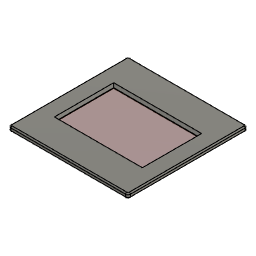
analog_projector (Autodesk Fusion 360 archive; units mm, degrees)
design "Film"
Autodesk Fusion 360 part; units mm, degrees
sketch "Sketch1" plane through (0, 0, 0) normal (0, 0, 1) x (1, 0, 0)
  line L0 (25, -25) -> (-25, -25)
  line L1 (-25, -25) -> (-25, 25)
  line L2 (-25, 25) -> (25, 25)
  line L3 (25, 25) -> (25, -25)
  line L4 (25, -25) -> (-25, 25) construction
  line L5 (-25, -25) -> (25, 25) construction
  dimension "d1" = 50
  dimension "d2" = 50
  constraint horizontal L0
  constraint perpendicular L0 L1
  constraint parallel L0 L2
  constraint parallel L1 L3
  constraint coincident L4 origin
  constraint coincident L5 origin
  measures "d1" distance of L1.end L2.end
  measures "d2" distance of L0.end L1.end
extrude "Extrude1" add sketch "Sketch1" along normal mid plane 2 makes body 1
sketch "Sketch2" plane through (0, 0, 1) normal (0, 0, 1) x (-1, 0, 0)
  line L0 (-25, -25) -> (25, -25)
  line L1 (25, -25) -> (25, 25)
  line L2 (25, 25) -> (-25, 25)
  line L3 (-25, 25) -> (-25, -25)
  line L4 (-17.5, 11.5) -> (17.5, 11.5)
  line L5 (17.5, 11.5) -> (17.5, -11.5)
  line L6 (17.5, -11.5) -> (-17.5, -11.5)
  line L7 (-17.5, -11.5) -> (-17.5, 11.5)
  line L8 (-17.5, 11.5) -> (17.5, -11.5) construction
  line L9 (17.5, 11.5) -> (-17.5, -11.5) construction
  dimension "d5" = 35
  dimension "d6" = 23
  constraint horizontal L4
  constraint perpendicular L4 L5
  constraint parallel L4 L6
  constraint parallel L5 L7
  constraint coincident L8 origin
  constraint coincident L9 origin
  measures "d5" distance of L5.end L6.end
  measures "d6" distance of L4.end L5.end
extrude "Extrude2" cut sketch "Sketch2" against normal up to surface (2 mm away) contours L4 L5 L6 L7 bodies 1
sketch "Sketch3" plane through (0, 0, 0) normal (0, 0, 1) x (1, 0, 0)
  line L0 (17.5, 11.5) -> (17.5, -11.5)
  line L1 (17.5, -11.5) -> (-17.5, -11.5)
  line L2 (-17.5, -11.5) -> (-17.5, 11.5)
  line L3 (-17.5, 11.5) -> (17.5, 11.5)
  line L4 (25, 25) -> (-25, 25)
  line L5 (-25, 25) -> (-25, -25)
  line L6 (-25, -25) -> (25, -25)
  line L7 (25, -25) -> (25, 25)
extrude "Extrude3" add sketch "Sketch3" along normal mid plane 0.2 separate body contours L0 L1 L2 L3 makes body 2
chamfer "Chamfer1" distance 0.9 angle 45 8 edges at (0, -11.5, -1) (17.5, 0, -1) (0, 11.5, -1) (-17.5, 0, -1) (0, -11.5, 1) (17.5, 0, 1) (-17.5, 0, 1) (0, 11.5, 1) on bodies 1
fillet "Fillet1" radius 1 4 edges at (25, -25, 0) (25, 25, 0) (-25, 25, 0) (-25, -25, 0) on bodies 1
fillet "Fillet2" radius 0.5 16 edges at (-24.7071, -24.7071, 1) (0, -25, 1) (24.7071, -24.7071, 1) (25, 0, 1) (24.7071, 24.7071, 1) (0, 25, 1) (-24.7071, 24.7071, 1) (-25, 0, 1) (-24.7071, 24.7071, -1) (0, 25, -1) (24.7071, 24.7071, -1) (25, 0, -1) (24.7071, -24.7071, -1) (0, -25, -1) (-24.7071, -24.7071, -1) (-25, 0, -1) on bodies 1

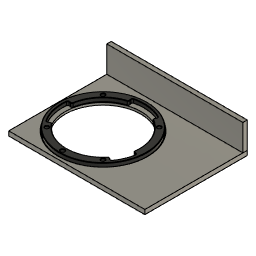
design "Lens Bracket" references "bantam tools desktop cnc milling machine"
Autodesk Fusion 360 part; units mm, degrees
sketch "Sketch1" plane through (0, 0, 0) normal (0, 0, 1) x (1, 0, 0) in component "Corner Bracket"
  line L0 (0, 0) -> (101, 0)
  line L1 (101, 0) -> (101, 76)
  line L2 (101, 76) -> (0, 76)
  line L3 (0, 76) -> (0, 0)
  dimension "d1" = 101
  dimension "d2" = 76
  constraint horizontal L0
  constraint vertical L1
  constraint horizontal L2
  constraint vertical L3
  constraint coincident L0.start L3.end
  measures "d1" distance of L0.start L0.end
  measures "d2" distance of L0.start L2.end
extrude "Extrude1" add sketch "Sketch1" along normal blind 3.3 makes body 1 in component "Corner Bracket"
sketch "Sketch2" plane through (0, 0, 3.3) normal (0, 0, 1) x (-1, 0, 0) in component "Corner Bracket"
  line L0 (0, -76) -> (0, 0)
  line L1 (0, 0) -> (-101, 0)
  line L2 (-101, 0) -> (-101, -76)
  line L3 (-101, -76) -> (0, -76)
  line L4 (0, -76) -> (-101, -76)
  line L5 (-101, -76) -> (-101, -72.75)
  line L6 (-101, -72.75) -> (0, -72.75)
  line L7 (0, -72.75) -> (0, -76)
  dimension "d5" = 3.25
  constraint horizontal L4
  constraint vertical L5
  constraint horizontal L6
  constraint vertical L7
  constraint coincident L2 L5.end
  constraint coincident L0.start L3.end
  measures "d5" distance of L4 L6
extrude "Extrude2" add sketch "Sketch2" along normal blind 19.5 contours L0 L2 L3 L4 L5 L6 L7 bodies 1 in component "Corner Bracket"
sketch "Sketch3" plane through (0, 0, 3.3) normal (0, 0, 1) x (-1, 0, 0) in component "Corner Bracket"
  line L0 (-101, -72.75) -> (0, -72.75)
  line L1 (0, -72.75) -> (0, 0)
  line L2 (0, 0) -> (-101, 0)
  line L3 (-101, 0) -> (-101, -72.75)
  circle A0 centre (-35, -35) radius 28.1
  line L4 (0, -69.5) -> (-101, -69.5)
  dimension "d8" = 56.2
  dimension "d9" = 3.25
  dimension "d10" = 34.5
  dimension "d11" = 35
  dimension "d13" = 35
  constraint coincident L1 L4.start
  constraint coincident L3 L4.end
  constraint perpendicular L3 L4
  measures "d8" diameter of A0
  measures "d9" distance of L0 L4
  measures "d10" distance of A0.centre L4
  measures "d11" distance of L2 A0.centre
  measures "d13" distance of L1 A0.centre
extrude "Extrude3" cut sketch "Sketch3" against normal up to surface (3.3 mm away) contours A0 bodies 1 in component "Corner Bracket"
sketch "Sketch4" plane through (0, 0, 3.3) normal (0, 0, 1) x (-1, 0, 0) in component "Corner Bracket"
  circle A0 centre (-35, -35) radius 28.1
  line L0 (-101, -72.75) -> (0, -72.75)
  line L1 (0, -72.75) -> (0, 0)
  line L2 (0, 0) -> (-101, 0)
  line L3 (-101, 0) -> (-101, -72.75)
  line L4 (-35, -35) -> (-35, 0) construction
  circle A1 centre (-35, -5) radius 1.25
  line L5 (-35, -35) -> (-6.7157, -6.7157) construction
  line L6 (-35, -35) -> (15, -35) construction
  circle A2 centre (-14.1403, -14.1403) radius 1.15
  dimension "d16" = 2.5
  dimension "d17" = 30
  dimension "d18" = 45
  dimension "d19" = 40
  dimension "d20" = 2.3
  dimension "d21" = 29.5
  constraint coincident A0.centre L4.start
  constraint coincident L2 L4.end
  constraint perpendicular L2 L4
  constraint coincident L4 A1.centre
  constraint horizontal L6
  constraint coincident L5 A2.centre
  measures "d16" diameter of A1
  measures "d17" distance of A0.centre A1.centre
  measures "d18" angle of L5 L6
  measures "d19" distance of A0.centre L5.end
  measures "d20" diameter of A2
  measures "d21" distance of A0.centre A2.centre
extrude "Extrude4" cut sketch "Sketch4" against normal up to surface (3.3 mm away) contours A1 | A2 bodies 1 in component "Corner Bracket"
pattern_circular "C-Pattern1" count 4 over 360 about axis through (35, 35, 3.3) along (0, 0, -1) of 1 faces at (12.9918, 14.1977, 1.1) on bodies 1 in component "Corner Bracket"
sketch "Sketch5" plane through (0, 0, 3.3) normal (0, 0, 1) x (-1, 0, 0) in component "Corner Bracket"
  circle A0 centre (-55.8597, -14.1403) radius 1.15
  circle A1 centre (-55.8597, -55.8597) radius 1.15
  circle A2 centre (-14.1403, -55.8597) radius 1.15
  circle A3 centre (-35, -5) radius 1.25
  circle A4 centre (-14.1403, -14.1403) radius 1.15
  circle A5 centre (-35, -35) radius 28.1
  line L0 (-101, -72.75) -> (0, -72.75)
  line L1 (0, -72.75) -> (0, 0)
  line L2 (0, 0) -> (-101, 0)
  line L3 (-101, 0) -> (-101, -72.75)
  circle A6 centre (-35, -35) radius 33
  dimension "d26" = 66
  constraint concentric A5 A6
  measures "d26" diameter of A6
extrude "Extrude5" cut sketch "Sketch5" against normal blind 1.6 contours A6 bodies 1 in component "Corner Bracket"
split "Split1" by plane through (0, 0, 3.3) normal (0, 0, 1) bodies 1 makes body 2 at (67.3333, 76, 9.8) in component "Corner Bracket"
ref_plane "WorkPlane1" through (35, 35, 2.7) normal (0, 0, 1) x (-1, 0, 0) in component "Corner Bracket"
sketch "Sketch6" plane through (35, 35, 2.7) normal (0, 0, 1) x (1, 0, 0) in component "Corner Bracket"
  circle A0 centre (20.8597, 20.8597) radius 1.15
  circle A1 centre (20.8597, -20.8597) radius 1.15
  circle A2 centre (0, -30) radius 1.25
  circle A3 centre (-20.8597, -20.8597) radius 1.15
  circle A4 centre (0, 0) radius 28.1
  circle A5 centre (-20.8597, 20.8597) radius 1.15
  circle A6 centre (0, 0) radius 33
  circle A7 centre (0, 0) radius 32.5
  circle A8 centre (0, 0) radius 27.1
  dimension "d30" = -0.5
  dimension "d31" = -1
extrude "Extrude6" add sketch "Sketch6" along normal blind 3 separate body contours A4 | A7 makes body 3 in component "Corner Bracket"
move_face "OffsetFaces1" offset -0.1 5 faces at (56.3326, 15.1886, 4.7) (36.2484, 4.9377, 4.7) (15.2889, 14.083, 4.7) (15.2889, 55.8023, 4.7) (54.7452, 55.5759, 4.7) on bodies 3 in component "Corner Bracket"
sketch "Sketch7" plane through (0, 0, 5.7) normal (0, 0, 1) x (-1, 0, 0) in component "Corner Bracket"
  circle A0 centre (-14.1403, -55.8597) radius 1.25
  circle A1 centre (-14.1403, -14.1403) radius 1.25
  circle A2 centre (-55.8597, -55.8597) radius 1.25
  circle A3 centre (-35, -35) radius 27.1
  circle A4 centre (-35, -5) radius 1.35
  circle A5 centre (-55.8597, -14.1403) radius 1.25
  circle A6 centre (-35, -35) radius 32.5
  circle A7 centre (-35, -35) radius 30.25
  line L0 (-35, -35) -> (-51, -35) construction
  line L1 (-35, -35) -> (-64.8478, -30.0836)
  line L2 (-35, -35) -> (-58.8625, -16.4085)
  line L3 (-35, -35) -> (-10.4096, -17.3825)
  line L4 (-35, -35) -> (-5.007, -38.9345)
  line L5 (-35, -35) -> (-27.1908, -64.2246)
  line L6 (-35, -35) -> (-49.3044, -61.6542)
  dimension "d35" = 60.5
  dimension "d36" = 61.779
  dimension "d37" = 104.961
  dimension "d38" = 172.527
  dimension "d39" = 144.381
  dimension "d40" = 9.353
  dimension "d41" = 37.922
  constraint concentric A3 A7
  constraint coincident A3.centre A6.centre
  constraint horizontal L0
  constraint coincident A7 L1.end
  constraint coincident A7 L2.end
  constraint coincident A7 L3.end
  constraint coincident A7 L4.end
  constraint coincident A7 L5.end
  constraint coincident A7 L6.end
  measures "d35" diameter of A7
  measures "d36" angle of L0 L6
  measures "d37" angle of L0 L5
  measures "d38" angle of L0 L4
  measures "d39" angle of L0 L3
  measures "d40" angle of L0 L1
  measures "d41" angle of L0 L2
extrude "Extrude7" cut sketch "Sketch7" against normal up to surface (3 mm away) contours A3 A7 L3 L4 | A3 A7 L5 L6 | A3 A7 L1 L2 bodies 3 in component "Corner Bracket"
fillet "Fillet1" radius 1 12 edges at (49.3044, 61.6542, 4.2) (47.8148, 58.8787, 4.2) (61.7397, 30.5956, 4.2) (64.8478, 30.0836, 4.2) (58.8625, 16.4085, 4.2) (56.3777, 18.3445, 4.2) (12.9703, 19.217, 4.2) (10.4096, 17.3825, 4.2) (5.007, 38.9345, 4.2) (8.1302, 38.5248, 4.2) (28.004, 61.1814, 4.2) (27.1908, 64.2246, 4.2) on bodies 3 in component "Corner Bracket"
chamfer "Chamfer1" distance 0.3 angle 45 50 edges at (59.313, 46.9703, 2.7) (62.0692, 30.8255, 2.7) (63.2765, 30.3424, 2.7) (64.5042, 29.831, 2.7) (62.7119, 22.8711, 2.7) (58.8149, 16.8323, 2.7) (57.6063, 17.3872, 2.7) (56.4323, 17.9464, 2.7) (34.4554, 7.9055, 2.7) (12.8997, 18.8215, 2.7) (11.7042, 18.3099, 2.7) (10.4742, 17.804, 2.7) (5.6579, 27.6445, 2.7) (5.2628, 38.5933, 2.7) (6.5859, 38.7274, 2.7) (7.8813, 38.8403, 2.7) (14.6271, 52.8706, 2.7) (27.6588, 61.3871, 2.7) (27.6019, 62.6862, 2.7) (27.5625, 64.0155, 2.7) (38.4927, 65.0477, 2.7) (48.8946, 61.5359, 2.7) (48.5513, 60.2511, 2.7) (48.198, 58.9996, 2.7) (4.6994, 23.2475, 2.7) (4.6994, 23.2475, 5.7) (59.313, 46.9703, 5.7) (62.0692, 30.8255, 5.7) (63.2765, 30.3424, 5.7) (64.5042, 29.831, 5.7) (62.7119, 22.8711, 5.7) (58.8149, 16.8323, 5.7) (57.6063, 17.3872, 5.7) (56.4323, 17.9464, 5.7) (34.4554, 7.9055, 5.7) (12.8997, 18.8215, 5.7) (11.7042, 18.3099, 5.7) (10.4742, 17.804, 5.7) (5.6579, 27.6445, 5.7) (5.2628, 38.5933, 5.7) (6.5859, 38.7274, 5.7) (7.8813, 38.8403, 5.7) (14.6271, 52.8706, 5.7) (27.6588, 61.3871, 5.7) (27.6019, 62.6862, 5.7) (27.5625, 64.0155, 5.7) (38.4927, 65.0477, 5.7) (48.8946, 61.5359, 5.7) (48.5513, 60.2511, 5.7) (48.198, 58.9996, 5.7) on bodies 3 in component "Corner Bracket"
chamfer "Chamfer2" distance 0.3 angle 45 10 edges at (54.6942, 14.5924, 2.7) (33.7414, 5.4882, 2.7) (12.9749, 14.5924, 2.7) (12.9749, 56.3117, 2.7) (54.6942, 56.3117, 2.7) (12.9749, 14.5924, 5.7) (33.7414, 5.4882, 5.7) (54.6942, 14.5924, 5.7) (54.6942, 56.3117, 5.7) (12.9749, 56.3117, 5.7) on bodies 3 in component "Corner Bracket"
component "Corner Bracket" placed x (1, 0, 0) y (0, 1, 0) z (0, 0, 1) at (0, 0, 0)
component "EF Mount" placed x (1, 0, 0) y (0, 1, 0) z (0, 0, 1) at (0, 0, 0)
